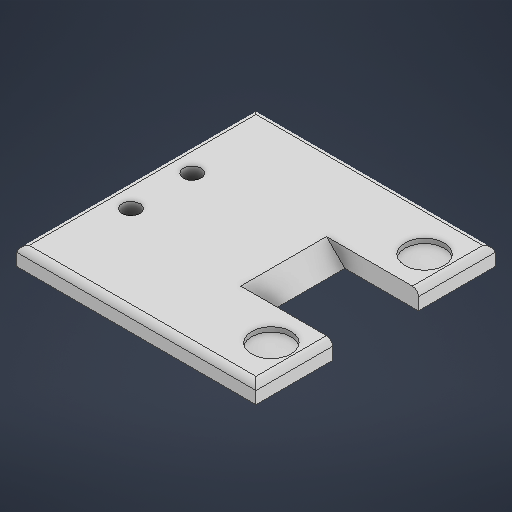
# Autodesk Inventor part: batterylidbb
Saved by Autodesk Inventor 2026.2 (Build 302298000, 298)
## iProperties
Created: 2026-10-11
Part Number: batterylidbb
Material: Generic
Document SubType Name: Modeling
Designer: Brian Wang
Density: 1 g/cm^3
Appearance: Default
Author: Brian Wang
Autodesk Inventor part; units mm, degrees
ref_plane "YZ Plane" through (0, 0, 0) normal (1, 0, 0) x (0, 1, 0)
ref_plane "XZ Plane" through (0, 0, 0) normal (0, 1, 0) x (-1, 0, 0)
ref_plane "XY Plane" through (0, 0, 0) normal (0, 0, 1) x (1, 0, 0)
sketch "Sketch1" plane through (0, 0, 0) normal (0, 1, 0) x (-1, 0, 0)
  line L0 (9.3919, 10.8111) -> (-30.6081, 10.8111)
  line L1 (-30.6081, 10.8111) -> (-30.6081, -29.1889)
  line L2 (-30.6081, -29.1889) -> (9.3919, -29.1889)
  line L3 (9.3919, -29.1889) -> (9.3919, 10.8111)
  point P0 (0, 0)
  dimension "d0" = 40
  dimension "d1" = 40
  constraints: 8 end point, 2 parallel, 1 horizontal, 1 perpendicular
  measures "d0" distance of L2.end L1.end
  measures "d1" distance of L1.end L0.end
extrude "Extrusion1" add sketch "Sketch1" along normal blind 3
sketch "Sketch2" plane through (0, 3, 0) normal (0, 1, 0) x (1, 0, 0)
  circle A0 centre (25.6081, -3.3111) radius 3.2
  circle A1 centre (25.6081, 21.6889) radius 3.2
  line L0 (-9.3919, -10.8111) -> (30.6081, -10.8111) projected
  line L1 (30.6081, -10.8111) -> (30.6081, 29.1889) projected
  point P0 (0, 0)
  dimension "d4" = 6.4
  dimension "d5" = 6.4
  dimension "d6" = 25
  dimension "d7" = 7.5
  dimension "d8" = 5
  constraints: 2 centre point, 1 vertical alignment
  measures "d4" diameter of A0
  measures "d5" diameter of A1
  measures "d6" distance of A1.centre A0.centre
  measures "d7" distance from line of L0 A0.centre
  measures "d8" distance from line of L1 A0.centre
extrude "Extrusion2" cut sketch "Sketch2" against normal blind 0.75
sketch "Sketch3" plane through (0, 3, 0) normal (0, 1, 0) x (1, 0, 0)
  circle A0 centre (-4.7919, 14.1889) radius 1.435
  circle A1 centre (-4.7919, 4.1889) radius 1.435
  line L0 (-9.3919, 29.1889) -> (-9.3919, -10.8111) projected
  line L1 (30.6081, 29.1889) -> (-9.3919, 29.1889) projected
  point P0 (0, 0)
  dimension "d11" = 2.87
  dimension "d12" = 2.87
  dimension "d13" = 4.6
  dimension "d14" = 10
  dimension "d15" = 15
  constraints: 2 centre point, 1 vertical alignment
  measures "d11" diameter of A0
  measures "d12" diameter of A1
  measures "d13" distance from line of L0 A0.centre
  measures "d14" distance of A1.centre A0.centre
  measures "d15" distance from line of L1 A0.centre
extrude "Extrusion3" cut sketch "Sketch3" against normal through all
sketch "Sketch4" plane through (0, 3, 0) normal (0, 1, 0) x (1, 0, 0)
  line L0 (-8.8919, 28.6889) -> (30.1081, 28.6889)
  line L1 (30.1081, 28.6889) -> (30.1081, -10.3111)
  line L2 (30.1081, -10.3111) -> (-8.8919, -10.3111)
  line L3 (-8.8919, -10.3111) -> (-8.8919, 28.6889)
  line L4 (-9.3919, 29.1889) -> (-9.3919, -10.8111) projected
  line L5 (-9.3919, -10.8111) -> (30.6081, -10.8111) projected
  line L6 (30.6081, 29.1889) -> (-9.3919, 29.1889) projected
  line L7 (30.6081, -10.8111) -> (30.6081, 29.1889) projected
  line L8 (-9.3919, 29.1889) -> (30.6081, 29.1889)
  line L9 (30.6081, 29.1889) -> (30.6081, -10.8111)
  line L10 (30.6081, -10.8111) -> (-9.3919, -10.8111)
  line L11 (-9.3919, -10.8111) -> (-9.3919, 29.1889)
  point P0 (0, 0)
  dimension "d18" = 39
  dimension "d19" = 39
  dimension "d20" = 0.5
  dimension "d21" = 0.5
  constraints: 16 end point, 4 parallel, 2 horizontal, 2 perpendicular
  measures "d18" distance of L0.start L0.end
  measures "d19" distance of L0.end L1.end
  measures "d20" distance between parallel lines of L4 L3
  measures "d21" distance between parallel lines of L5 L2
extrude "Extrusion4" cut sketch "Sketch4" against normal blind 10
fillet "Fillet1" radius 1 4 edges at (30.1081, 3, -9.1889) (10.6081, 3, 10.3111) (-8.8919, 3, -9.1889) (10.6081, 3, -28.6889)
sketch "Sketch5" plane through (0, 0, 0) normal (0, -1, 0) x (1, 0, 0)
  line L0 (30.1081, -28.6889) -> (30.1081, 10.3111) projected
  line L1 (30.1081, -2.1889) -> (18.1081, -2.1889)
  line L2 (18.1081, -2.1889) -> (18.1081, -16.1889)
  line L3 (18.1081, -16.1889) -> (30.1081, -16.1889)
  line L4 (30.1081, -16.1889) -> (30.1081, -2.1889)
  line L5 (-8.8919, -28.6889) -> (30.1081, -28.6889) projected
  point P0 (0, 0)
  dimension "d25" = 14
  dimension "d26" = 12.5
  dimension "d27" = 12
  constraints: 8 end point, 2 parallel, 1 horizontal, 1 perpendicular, 1 point on line
  measures "d25" distance of L2.end L1.end
  measures "d26" distance between parallel lines of L5 L3
  measures "d27" distance of L2.end L3.end
extrude "Extrusion5" cut sketch "Sketch5" against normal blind 10
chamfer "Chamfer1" distance 3 angle 45 1 edges at (18.1081, 3, -9.1889)
body "Solid1"
